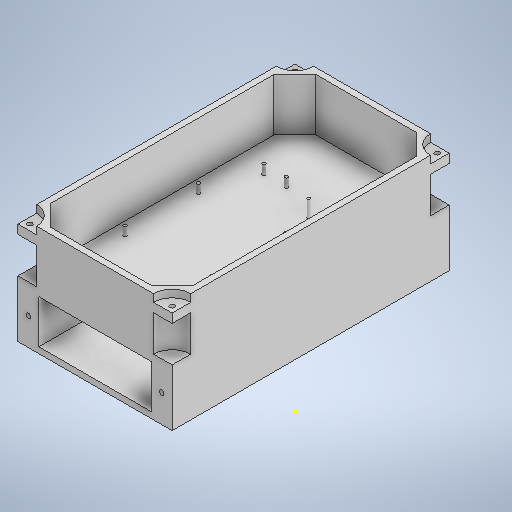
# Autodesk Inventor part: part3
Saved by Autodesk Inventor 2025 (Build 290162000, 162)
## iProperties
Created: 2026-05-18
Part Number: part3
Material: Generic
Document SubType Name: Modeling
Designer: User
Density: 1 g/cm^3
Appearance: Default
Author: User
Autodesk Inventor part; units mm, degrees
ref_plane "YZ Plane" through (0, 0, 0) normal (1, 0, 0) x (0, 1, 0)
ref_plane "XZ Plane" through (0, 0, 0) normal (0, 1, 0) x (-1, 0, 0)
sketch "Sketch1" plane through (0, 0, 0) normal (0, 1, 0) x (-1, 0, 0)
  line L0 (0, 185) -> (-103, 185)
  line L1 (-103, 185) -> (-103, 0)
  line L2 (-103, 0) -> (0, 0)
  line L3 (0, 0) -> (0, 185)
  dimension "d0" = 185
  dimension "d1" = 103
  dimension "d2" = 0
  constraints: 8 end point, 2 parallel, 1 horizontal, 1 perpendicular
  measures "d0" distance of L2.end L0.start
  measures "d1" distance of L1.end L2.end
  measures "d2" distance of L2.end point (0, 0)
extrude "Extrusion1" add sketch "Sketch1" along normal blind 73
sketch "Sketch2" plane through (0, 73, 0) normal (0, 1, 0) x (1, 0, 0)
  line L0 (4, -181) -> (99, -181)
  line L1 (99, -181) -> (99, -4)
  line L2 (99, -4) -> (4, -4)
  line L3 (4, -4) -> (4, -181)
  line L4 (0, 0) -> (0, -185) projected
  line L5 (0, -185) -> (103, -185) projected
  line L6 (103, -185) -> (103, 0) projected
  line L7 (103, 0) -> (0, 0) projected
  point P0 (51.5, -4)
  dimension "d5" = 4
  dimension "d6" = 4
  dimension "d7" = 4
  dimension "d8" = 4
  constraints: 8 end point, 2 parallel, 1 horizontal, 1 midpoint, 1 perpendicular
  measures "d5" distance between parallel lines of L4 L3
  measures "d6" distance between parallel lines of L5 L0
  measures "d7" distance between parallel lines of L6 L1
  measures "d8" distance from line of L7 point (51.5, -4)
sketch "Sketch3" plane through (103, 0, 185) normal (1, 0, 0) x (0, 0, -1)
  point P0 (185, 0)
shell "Shell2" thickness 4 removed faces 1 at (34.3333, 73, 61.6667)
sketch "Sketch4" plane through (0, 0, 185) normal (0, 0, 1) x (1, 0, 0)
  line L0 (99, 4) -> (99, 73) projected
  line L1 (4, 33) -> (99, 33)
  line L2 (99, 33) -> (99, 4)
  line L3 (99, 4) -> (4, 4)
  line L4 (4, 4) -> (4, 33)
  line L5 (4, 4) -> (4, 73) projected
  line L6 (0, 0) -> (103, 0) projected
  line L7 (0, 0) -> (0, 73) projected
  dimension "d11" = 4
  dimension "d12" = 29
  dimension "d13" = 4
  constraints: 8 end point, 2 parallel, 1 collinear, 1 horizontal, 1 perpendicular, 1 point on line
  measures "d11" distance between parallel lines of L6 L3
  measures "d12" distance between parallel lines of L1 L3
  measures "d13" distance between parallel lines of L7 L4
sketch "Sketch5" plane through (0, 0, 185) normal (0, 0, 1) x (1, 0, 0)
  point P0 (0, 0)
extrude "Extrusion2" cut sketch "Sketch4" against normal blind 73
sketch "Sketch6" plane through (0, 73, 0) normal (0, 1, 0) x (1, 0, 0)
  line L0 (4, -4) -> (4, -46.9899)
  line L1 (4, -181) -> (4, -4) projected
  line L2 (4, -18) -> (4, -4)
  line L3 (18, -4) -> (4, -4)
  line L4 (4, -18) -> (18, -4)
  line L5 (4, -4) -> (99, -4) projected
  line L6 (99, -4) -> (99, -18)
  line L7 (99, -18) -> (85, -4)
  line L8 (85, -4) -> (99, -4)
  line L9 (4, -181) -> (18, -181)
  line L10 (18, -181) -> (4, -167)
  line L11 (4, -167) -> (4, -181)
  line L12 (85, -181) -> (99, -181)
  line L13 (99, -181) -> (99, -167)
  line L14 (99, -167) -> (85, -181)
  line L15 (99, -181) -> (4, -181) projected
  line L16 (99, -4) -> (99, -181) projected
  point P0 (0, 0)
  point P1 (4, -167)
  point P2 (4, -181)
  dimension "d16" = 14
  dimension "d17" = 14
  dimension "d24" = 0
  dimension "d25" = 0
  dimension "d26" = 90
  dimension "d27" = 14
  dimension "d28" = 14
  dimension "d29" = 0
  dimension "d34" = 0
  dimension "d41" = 90
  dimension "d44" = 0
  dimension "d46" = 42.9899
  dimension "d47" = 90
  dimension "d48" = 14
  dimension "d49" = 14
  dimension "d50" = 0
  dimension "d51" = 0
  dimension "d52" = 14
  dimension "d53" = 14
  dimension "d54" = 0
  dimension "d55" = 0
  constraints: 26 end point, 2 horizontal, 2 perpendicular, 2 vertical, 1 point on line
  measures "d16" distance of L2.start L2.end
  measures "d17" distance of L3.start L2.end
  measures "d24" distance of L1.end L2.end
  measures "d25" distance between parallel lines of L5 L3
  measures "d26" angle of L6 L8
  measures "d27" distance of L7.end L6.start
  measures "d28" distance of L6.start L6.end
  measures "d29" distance of L5.end L6.start
  measures "d34" distance from line of L5 L7.end
  measures "d41" angle of L3 L0
  measures "d44" distance from line of L0.start L3
  measures "d46" distance from line of L0.end L5
  measures "d47" angle of L9 L11
  measures "d48" distance of L9.start L9.end
  measures "d49" distance of L10.end L9.start
  measures "d50" distance of L1.start L9.start
  measures "d51" distance from line of L1 L10.end
  measures "d52" distance of L12.start L12.end
  measures "d53" distance of L12.end L13.end
  measures "d54" distance from line of L15 L12.end
  measures "d55" distance from line of L16 L12.end
extrude "Extrusion3" add sketch "Sketch6" against normal blind 39 contours L3 L4 L0 | L5 L6 L7 | L10 L9 L1 | L13 L12 L14
sketch "Sketch7" plane through (4, 4, 4) normal (0, 1, 0) x (1, 0, 0)
  point P0 (-4, 4)
sketch "Sketch8" plane through (99, 4, 4) normal (-1, 0, 0) x (0, 0, 1)
  line L0 (1, 30) -> (181, 30)
  line L1 (181, 29) -> (181, 0) projected
  line L2 (181, 0) -> (0, 0) projected
  point P0 (-4, -4)
  dimension "d58" = 180
  dimension "d60" = 30
  constraints: 2 end point, 1 parallel, 1 point on line
  measures "d58" distance of L0.start L0.end
  measures "d60" distance between parallel lines of L0 L2
ref_plane "Work Plane1" through (4, 38, 4) normal (0, 1, 0) x (1, 0, 0)
sketch "Sketch9" plane through (4, 38, 4) normal (0, 1, 0) x (1, 0, 0)
  line L0 (99, 4) -> (-4, 4)
  line L1 (-4, 4) -> (-4, -161)
  line L2 (-4, -161) -> (99, -161)
  line L3 (99, -161) -> (99, 4)
  line L4 (99, 4) -> (-4, 4) projected
  line L5 (-4, 4) -> (-4, -181) projected
  line L6 (95, -181) -> (95, 0) projected
  line L7 (79, -161) -> (95, -161)
  line L8 (95, -161) -> (95, -177)
  line L9 (95, -177) -> (79, -177)
  line L10 (79, -177) -> (79, -161)
  line L11 (0, -163) -> (0, -14) projected
  line L12 (81, -177) -> (14, -177) projected
  line L13 (0, -161) -> (16, -161)
  line L14 (16, -161) -> (16, -177)
  line L15 (16, -177) -> (0, -177)
  line L16 (0, -177) -> (0, -161)
  point P0 (95, -161)
  point P1 (0, -163)
  point P2 (14, -177)
  point P3 (95, -161)
  point P4 (16, -161)
  dimension "d62" = 165
  dimension "d63" = 103
  dimension "d64" = 0
  dimension "d65" = 0
  dimension "d68" = 16
  dimension "d70" = 16
  dimension "d71" = 16
  constraints: 22 end point, 5 parallel, 4 horizontal, 3 perpendicular, 3 point on line, 5 other
  measures "d62" distance of L0.end L1.end
  measures "d63" distance of L0.start L0.end
  measures "d64" distance between parallel lines of L4 L0
  measures "d65" distance between parallel lines of L1 L5
  measures "d68" distance between parallel lines of L6 L10
  measures "d70" length of L9
  measures "d71" distance between parallel lines of L16 L14
extrude "Extrusion4" add sketch "Sketch9" against normal blind 4 contours L3 L2 L1 L0 | L6 L9 L10 L2 | L2 L14 L12 L15 L16 L11
sketch "Sketch12" plane through (0, 73, 0) normal (0, 1, 0) x (1, 0, 0)
  line L0 (103, -185) -> (103, 0) projected
  circle A0 centre (103, 0) radius 12.5
  circle A1 centre (103, -185) radius 12.5
  line L1 (0, -185) -> (103, -185) projected
  circle A2 centre (0, -185) radius 12.5
  line L2 (103, 0) -> (0, 0) projected
  circle A3 centre (0, 0) radius 12.5
  point P0 (90.5, -185)
  point P1 (103, -172.5)
  point P2 (90.5, 0)
  point P3 (103, -12.5)
  dimension "d72" = 25
  dimension "d73" = 25
  dimension "d74" = 25
  dimension "d75" = 25
  constraints: 4 centre point, 2 coincident
  measures "d72" diameter of A0
  measures "d73" diameter of A1
  measures "d74" diameter of A2
  measures "d75" diameter of A3
extrude "Extrusion5" cut sketch "Sketch12" against normal blind 5
sketch "Sketch14" plane through (4, 38, 4) normal (0, 1, 0) x (1, 0, 0)
  line L0 (99, -181) -> (99, 4) projected
  circle A0 centre (99, 4) radius 12.5
  circle A1 centre (99, -181) radius 12.5
  circle A2 centre (-4, 4) radius 12.5
  circle A3 centre (-4, -181) radius 12.5
  point P0 (-4, 4)
  dimension "d79" = 25
  dimension "d80" = 25
  dimension "d81" = 25
  dimension "d82" = 25
  constraints: 4 centre point, 2 coincident
  measures "d79" diameter of A0
  measures "d80" diameter of A1
  measures "d81" diameter of A2
  measures "d82" diameter of A3
extrude "Extrusion6" cut sketch "Sketch14" along normal blind 24
sketch "Sketch15" plane through (0, 68, 0) normal (0, 1, 0) x (1, 0, 0)
  line L0 (4, -185) -> (4, -181) projected
  circle A0 centre (4, -181) radius 1.6
  line L1 (4, -4) -> (4, -181) projected
  circle A1 centre (4, -4) radius 1.6
  line L2 (99, -181) -> (99, -4) projected
  circle A2 centre (99, -4) radius 1.6
  circle A3 centre (99, -181) radius 1.6
  point P0 (0, 0)
  dimension "d85" = 3.2
  dimension "d86" = 3.2
  dimension "d87" = 3.2
  dimension "d88" = 3.2
  constraints: 4 centre point, 1 coincident
  measures "d85" diameter of A0
  measures "d86" diameter of A1
  measures "d87" diameter of A2
  measures "d88" diameter of A3
extrude "Extrusion7" cut sketch "Sketch15" against normal blind 12
sketch "Sketch16" plane through (4, 38, 4) normal (0, 1, 0) x (1, 0, 0)
  circle A0 centre (8.5, -73) radius 1.1
  line L0 (0, -163) -> (0, -14) projected
  line L1 (14, 0) -> (81, 0) projected
  circle A1 centre (66.5, -73) radius 1.1
  line L2 (95, -14) -> (95, -163) projected
  circle A2 centre (8.5, -122) radius 1.1
  line L3 (81, -177) -> (14, -177) projected
  circle A3 centre (66.5, -122) radius 1.1
  circle A4 centre (78.25, -50) radius 0.975
  circle A5 centre (59.25, -50) radius 0.975
  circle A6 centre (34.25, -40) radius 1.1
  circle A7 centre (19.25, -40) radius 1.1
  point P0 (-4, 4)
  dimension "d91" = 8.5
  dimension "d92" = 2.2
  dimension "d96" = 2.2
  dimension "d97" = 8.5
  dimension "d98" = 55
  dimension "d99" = 2.2
  dimension "d101" = 55
  dimension "d102" = 2.2
  dimension "d105" = 58
  dimension "d106" = 58
  dimension "d107" = 49
  dimension "d108" = 49
  dimension "d109" = 23
  dimension "d110" = 16.75
  dimension "d111" = 1.95
  dimension "d112" = 23
  dimension "d113" = 19
  dimension "d114" = 1.95
  dimension "d115" = 10
  dimension "d116" = 10
  dimension "d117" = 2.2
  dimension "d118" = 2.2
  dimension "d119" = 15
  dimension "d120" = 25
  constraints: 8 centre point
  measures "d91" distance from line of L0 A0.centre
  measures "d92" diameter of A0
  measures "d96" diameter of A1
  measures "d97" distance from line of L0 A2.centre
  measures "d98" distance from line of L3 A2.centre
  measures "d99" diameter of A2
  measures "d101" distance from line of L3 A3.centre
  measures "d102" diameter of A3
  measures "d105" distance of A1.centre A0.centre
  measures "d106" distance of A3.centre A2.centre
  measures "d107" distance of A2.centre A0.centre
  measures "d108" distance of A1.centre A3.centre
  measures "d109" vertical distance of A4.centre A1.centre
  measures "d110" distance from line of L2 A4.centre
  measures "d111" diameter of A4
  measures "d112" vertical distance of A1.centre A5.centre
  measures "d113" distance of A4.centre A5.centre
  measures "d114" diameter of A5
  measures "d115" vertical distance of A5.centre A6.centre
  measures "d116" vertical distance of A5.centre A7.centre
  measures "d117" diameter of A6
  measures "d118" diameter of A7
  measures "d119" distance of A7.centre A6.centre
  measures "d120" horizontal distance of A5.centre A6.centre
extrude "Extrusion8" add sketch "Sketch16" along normal blind 6 contours A0 | A1 | A2 | A3 | A6 | A7
extrude "Extrusion9" add sketch "Sketch16" along normal blind 11 contours A4 | A5
sketch "Sketch18" plane through (0, 0, 185) normal (0, 0, 1) x (1, 0, 0)
  line L0 (99, 4) -> (89, 4)
  line L1 (89, 4) -> (89, 33)
  line L2 (89, 33) -> (99, 33)
  line L3 (99, 33) -> (99, 4)
  line L4 (4, 33) -> (99, 33) projected
  line L5 (4, 4) -> (4, 33) projected
  line L6 (4, 4) -> (14, 4)
  line L7 (14, 4) -> (14, 33)
  line L8 (14, 33) -> (4, 33)
  line L9 (4, 33) -> (4, 4)
  point P0 (0, 0)
  point P1 (9, 33)
  dimension "d123" = 0
  dimension "d127" = 0
  dimension "d128" = 75
  dimension "d129" = 10
  constraints: 16 end point, 4 parallel, 2 horizontal, 2 perpendicular, 1 midpoint
  measures "d123" distance between parallel lines of L4 L2
  measures "d127" distance from line of L4 point (9, 33)
  measures "d128" distance between parallel lines of L1 L7
  measures "d129" distance between parallel lines of L5 L7
extrude "Extrusion10" add sketch "Sketch18" against normal blind 180
sketch "Sketch20" plane through (0, 0, 185) normal (0, 0, 1) x (1, 0, 0)
  line L0 (89, 4) -> (14, 4) projected
  line L1 (0, 0) -> (0, 38) projected
  line L2 (103, 0) -> (103, 38) projected
  point P0 (7, 18.5)
  point P1 (96, 18.5)
  dimension "d130" = 14.5
  dimension "d131" = 7
  dimension "d132" = 7
  dimension "d133" = 14.5
  measures "d130" distance from line of L0 point (7, 18.5)
  measures "d131" distance from line of L1 point (7, 18.5)
  measures "d132" distance from line of L2 point (96, 18.5)
  measures "d133" distance from line of L0 point (96, 18.5)
hole "Hole1" at (7, 18.5, 185) at (96, 18.5, 185) direction (0, 0, -1) diameter 3.242 depth 11.8 thread size "M4x0.7" class "6H" standard "ISO Metric profile"
sketch "Sketch21" plane through (85, 38, 181) normal (-0.7071068, 0, -0.7071068) x (-0.7071068, 0, 0.7071068)
  point P0 (-67.8823, -38)
body "Solid1"
